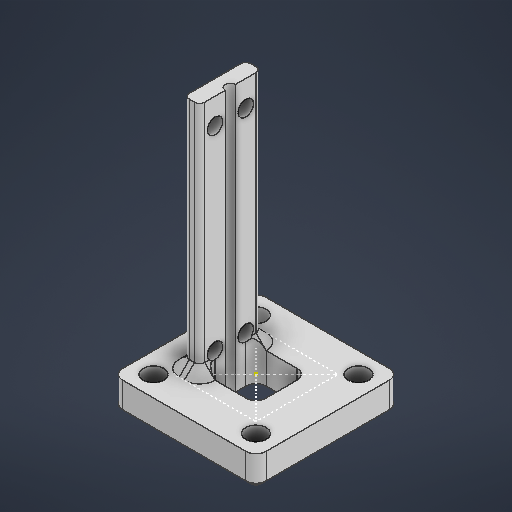
# Autodesk Inventor part: signal machine
Saved by Autodesk Inventor 2026.2 (Build 302298010, 298A)
## iProperties
Created: 2026-05-04
Part Number: signal machine
Material: 일반
Document SubType Name: Modeling
Designer: work
Density: 1 g/cm^3
Appearance: 기본값
Author: work
Autodesk Inventor part; units mm, degrees
ref_plane "YZ Plane" through (0, 0, 0) normal (1, 0, 0) x (0, 1, 0)
ref_plane "XZ Plane" through (0, 0, 0) normal (0, 1, 0) x (-1, 0, 0)
ref_plane "XY Plane" through (0, 0, 0) normal (0, 0, 1) x (1, 0, 0)
sketch "스케치1" plane through (0, 0, 0) normal (0, 1, 0) x (-1, 0, 0)
  line L0 (-10, 10) -> (10, 10) construction
  line L1 (10, 10) -> (10, -10) construction
  line L2 (10, -10) -> (-10, -10) construction
  line L3 (-10, -10) -> (-10, 10) construction
  line L4 (-10, 10) -> (10, -10) construction
  line L5 (10, 10) -> (-10, -10) construction
  line L6 (-3, 5) -> (3, 5)
  line L7 (5, 3) -> (5, -3)
  line L8 (3, -5) -> (-3, -5)
  line L9 (-5, -3) -> (-5, 3)
  line L10 (-5, 5) -> (5, -5) construction
  line L11 (5, 5) -> (-5, -5) construction
  circle A0 centre (10, 10) radius 2
  circle A1 centre (10, -10) radius 2
  circle A2 centre (-10, -10) radius 2
  circle A3 centre (-10, 10) radius 2
  line L12 (-14, 14) -> (14, 14)
  line L13 (14, 14) -> (14, -14)
  line L14 (14, -14) -> (-14, -14)
  line L15 (-14, -14) -> (-14, 14)
  line L16 (-14, 14) -> (14, -14) construction
  line L17 (14, 14) -> (-14, -14) construction
  arc A4 (5, 3) -> (3, 5) centre (3, 3) ccw
  arc A5 (-3, 5) -> (-5, 3) centre (-3, 3) ccw
  arc A6 (-5, -3) -> (-3, -5) centre (-3, -3) ccw
  arc A7 (3, -5) -> (5, -3) centre (3, -3) ccw
  point P0 (0, 0)
  dimension "d0" = 20
  dimension "d1" = 20
  dimension "d2" = 10
  dimension "d3" = 10
  dimension "d4" = 4
  dimension "d5" = 4
  dimension "d6" = 4
  dimension "d7" = 4
  dimension "d8" = 4
  dimension "d9" = 4
  dimension "d10" = 2
  constraints: 36 end point, 8 centre point, 8 point on circle, 8 point on line, 8 tangent, 6 midpoint, 6 parallel, 4 coincident, 3 equal radius, 3 horizontal, 3 perpendicular
  measures "d0" distance of L1.end L2.end
  measures "d1" distance of L0.end L1.end
  measures "d2" distance of L10.end L11.end
  measures "d3" distance of L11.start L10.end
  measures "d4" diameter of A0
  measures "d5" diameter of A1
  measures "d6" diameter of A2
  measures "d7" diameter of A3
  measures "d8" distance between parallel lines of L13 L1
  measures "d9" distance between parallel lines of L14 L2
  measures "d10" radius of A4
extrude "돌출1" add sketch "스케치1" along normal blind 6
sketch "스케치2" plane through (0, 6, 0) normal (0, 1, 0) x (1, 0, 0)
  point P0 (0, 0)
sketch "스케치3" plane through (-5, 0, 3) normal (1, 0, 0) x (0, 0, -1)
  line L0 (3, 0) -> (3, 9) construction
  line L1 (0, 9) -> (6, 9) construction
  circle A0 centre (0, 9) radius 1.5
  circle A1 centre (6, 9) radius 1.5
  line L2 (-3, 12) -> (9, 12)
  line L3 (9, 12) -> (9, 0)
  line L4 (9, 0) -> (-3, 0)
  line L5 (-3, 0) -> (-3, 12)
  point P0 (3, 12)
  dimension "d13" = 9
  dimension "d14" = 3
  dimension "d15" = 3
  dimension "d16" = 6
  dimension "d17" = 3
  dimension "d18" = 3
  constraints: 12 end point, 3 midpoint, 2 centre point, 2 coincident, 2 horizontal, 2 parallel, 1 perpendicular, 1 vertical
  measures "d13" distance of L0.start L0.end
  measures "d14" diameter of A0
  measures "d15" diameter of A1
  measures "d16" distance of L1.start L1.end
  measures "d17" distance from line of point (3, 12) L1
  measures "d18" distance from line of L3 L1.end
extrude "돌출2" add sketch "스케치3" against normal blind 3
sketch "스케치4" plane through (-5, 12, 6) normal (0, 1, 0) x (1, 0, 0)
  line L0 (0, 3) -> (0, 9) projected
  circle A0 centre (0, 6) radius 1
  point P0 (5, 6)
  point P1 (0, 7)
  point P2 (0, 5)
  dimension "d21" = 2
  constraints: 1 centre point, 1 midpoint
  measures "d21" diameter of A0
extrude "돌출3" cut sketch "스케치4" against normal through all contours A0 L0 picked at (-0.3008, 5.7602)
fillet "모깎기1" radius 1 4 edges at (-8, 9, 6) (-5, 9, 6) (-5, 9, -6) (-8, 9, -6)
fillet "모깎기3" radius 2 4 edges at (-14, 3, 14) (-14, 3, -14) (14, 3, -14) (14, 3, 14)
sketch "스케치5" plane through (0, 6, 0) normal (0, 1, 0) x (1, 0, 0)
  line L0 (8, -8) -> (-8, -8) construction
  line L1 (-8, -8) -> (-8, 8) construction
  line L2 (-8, 8) -> (8, 8) construction
  line L3 (8, 8) -> (8, -8) construction
  line L4 (8, -8) -> (-8, 8) construction
  line L5 (-8, -8) -> (8, 8) construction
  line L6 (-8, -5) -> (-8, 5) construction
  point P0 (0, 0)
  point P1 (-8, 0)
  constraints: 12 end point, 4 midpoint, 2 parallel, 2 perpendicular, 1 horizontal
sketch "스케치6" plane through (-5, 12, 0) normal (0, 1, 0) x (1, 0, 0)
  arc A0 (-2, 6) -> (-3, 5) centre (-2, 5) ccw projected
  line L0 (-3, -5) -> (-3, 5) projected
  arc A1 (-3, -5) -> (-2, -6) centre (-2, -5) ccw projected
  line L1 (-1, -6) -> (-2, -6) projected
  arc A2 (-1, -6) -> (0, -5) centre (-1, -5) ccw projected
  line L2 (0, -1) -> (0, -5) projected
  arc A3 (0, 1) -> (0, -1) centre (0, 0) ccw projected
  line L3 (0, 5) -> (0, 1) projected
  arc A4 (0, 5) -> (-1, 6) centre (-1, 5) ccw projected
  line L4 (-1, 6) -> (-2, 6) projected
  point P0 (5, 0)
extrude "돌출4" add sketch "스케치6" along normal blind 40
sketch "스케치7" plane through (-5, 0, 3) normal (1, 0, 0) x (0, 0, -1)
  line L0 (0, 47) -> (6, 47) construction
  circle A0 centre (0, 47) radius 1.5
  circle A1 centre (6, 47) radius 1.5
  line L1 (3, 47) -> (3, 9) construction
  line L2 (4, 0) -> (4, 52) projected
  line L3 (-2, 6) -> (-2, 52) projected
  line L4 (0, 6) -> (-2, 6) projected
  line L5 (0, 0) -> (0, 6) projected
  line L6 (0, 0) -> (2, 0) projected
  line L7 (2, 0) -> (2, 52) projected
  line L8 (-2, 52) -> (2, 52) projected
  circle A2 centre (0, 9) radius 1.5 projected
  line L9 (8, 6) -> (8, 52) projected
  line L10 (4, 52) -> (8, 52) projected
  line L11 (4, 0) -> (4, 52) projected
  line L12 (4, 0) -> (6, 0) projected
  line L13 (6, 0) -> (6, 6) projected
  line L14 (8, 6) -> (6, 6) projected
  circle A3 centre (6, 9) radius 1.5 projected
  line L15 (6, 9) -> (0, 9) construction
  point P0 (3, 0)
  dimension "d29" = 3
  dimension "d30" = 3
  dimension "d31" = 38
  constraints: 6 end point, 2 centre point, 2 coincident, 2 horizontal, 2 midpoint, 2 parallel
  measures "d29" diameter of A0
  measures "d30" diameter of A1
  measures "d31" distance of L1.end L1.start
extrude "돌출5" cut sketch "스케치7" against normal through all contours A0 | A1
chamfer "모따기1" distance 1 angle 45 8 edges at (14, 0, 0) (13.4142, 0, -13.4142) (0, 0, -14) (-13.4142, 0, -13.4142) (-14, 0, 0) (-13.4142, 0, 13.4142) (0, 0, 14) (13.4142, 0, 13.4142)
chamfer "모따기2" distance 2 angle 45 9 edges at (-5.2929, 6, -5.7071) (-6.5, 6, -6) (-7.7071, 6, -5.7071) (-8, 6, 0) (-7.7071, 6, 5.7071) (-6.5, 6, 6) (-5.2929, 6, 5.7071) (-5, 6, 4) (-5, 6, -4)
sketch "스케치8" plane through (-8, 0, 3) normal (-1, 0, 0) x (0, 0, 1)
  line L0 (-7.118, 8) -> (-8, 8) projected
  arc A0 (-4.882, 8) -> (-7.118, 8) centre (-6, 9) ccw projected
  line L1 (-1.118, 8) -> (-4.882, 8) projected
  arc A1 (1.118, 8) -> (-1.118, 8) centre (0, 9) ccw projected
  line L2 (2, 8) -> (1.118, 8) projected
  line L3 (2, 8) -> (2, 52) projected
  line L4 (-8, 52) -> (2, 52) projected
  line L5 (-8, 8) -> (-8, 52) projected
  circle A2 centre (0, 47) radius 1.5 projected
  circle A3 centre (-6, 47) radius 1.5 projected
  line L6 (-6, 6) -> (0, 6) projected
  circle A4 centre (-6, 9) radius 3
  circle A5 centre (0, 9) radius 3
  point P0 (-3, 0)
  point P1 (-3, 9)
  constraints: 2 coincident, 1 centre point, 3 other
extrude "돌출6" cut sketch "스케치8" along normal blind 10 contours A0 L1 A4 L5 L0 | L0 L5 A4 L1 A0 | A5 L3 L2 A1 L1 | L1 A1 L2 L3 A5
